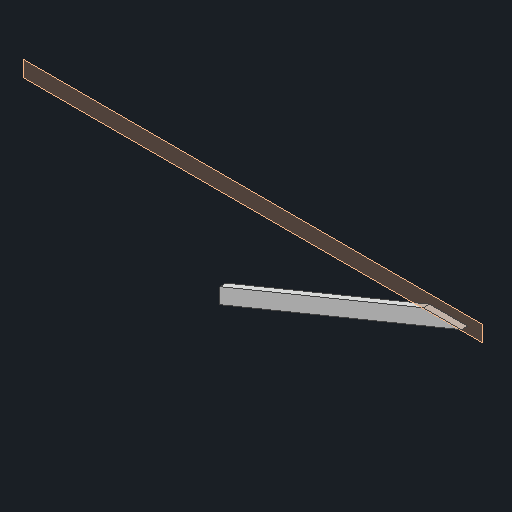
# Autodesk Inventor part: Top side diagonals
Saved by Autodesk Inventor 2027 (Build 310192000, 192)
## iProperties
Created: 2026-10-18
Part Number: Top side diagonals
Material: Generic
Document SubType Name: Modeling
Designer: lucas
Density: 1 g/cm^3
Appearance: Default
Author: lucas
Autodesk Inventor part; units mm, degrees
ref_plane "YZ Plane" through (0, 0, 0) normal (1, 0, 0) x (0, 1, 0)
ref_plane "XZ Plane" through (0, 0, 0) normal (0, 1, 0) x (-1, 0, 0)
ref_plane "XY Plane" through (0, 0, 0) normal (0, 0, 1) x (1, 0, 0)
ref_plane "Work Plane1" through (0, 0, 0) normal (0, 0, 1) x (1, 0, 0)
sketch "Sketch1" plane through (0, 0, 0) normal (0, 0, 1) x (1, 0, 0)
  line L0 (1282.7, -44.45) -> (-203.2, -654.05)
  line L1 (-209.1177, -560.3872) -> (1048.4792, -44.45)
  line L2 (-203.2, -654.05) -> (-203.2, -557.9594)
  line L3 (-203.2, -557.9594) -> (-209.1177, -560.3872)
  line L4 (1282.7, -44.45) -> (1048.4792, -44.45)
  point P0 (0, 0)
  dimension "d0" = 88.9
  constraints: 10 end point, 1 collinear, 1 horizontal, 1 parallel, 1 vertical, 2 other
  measures "d0" distance between parallel lines of L0 L1
extrude "Extrusion1" add sketch "Sketch1" against normal blind 38.1
body "Solid1"
